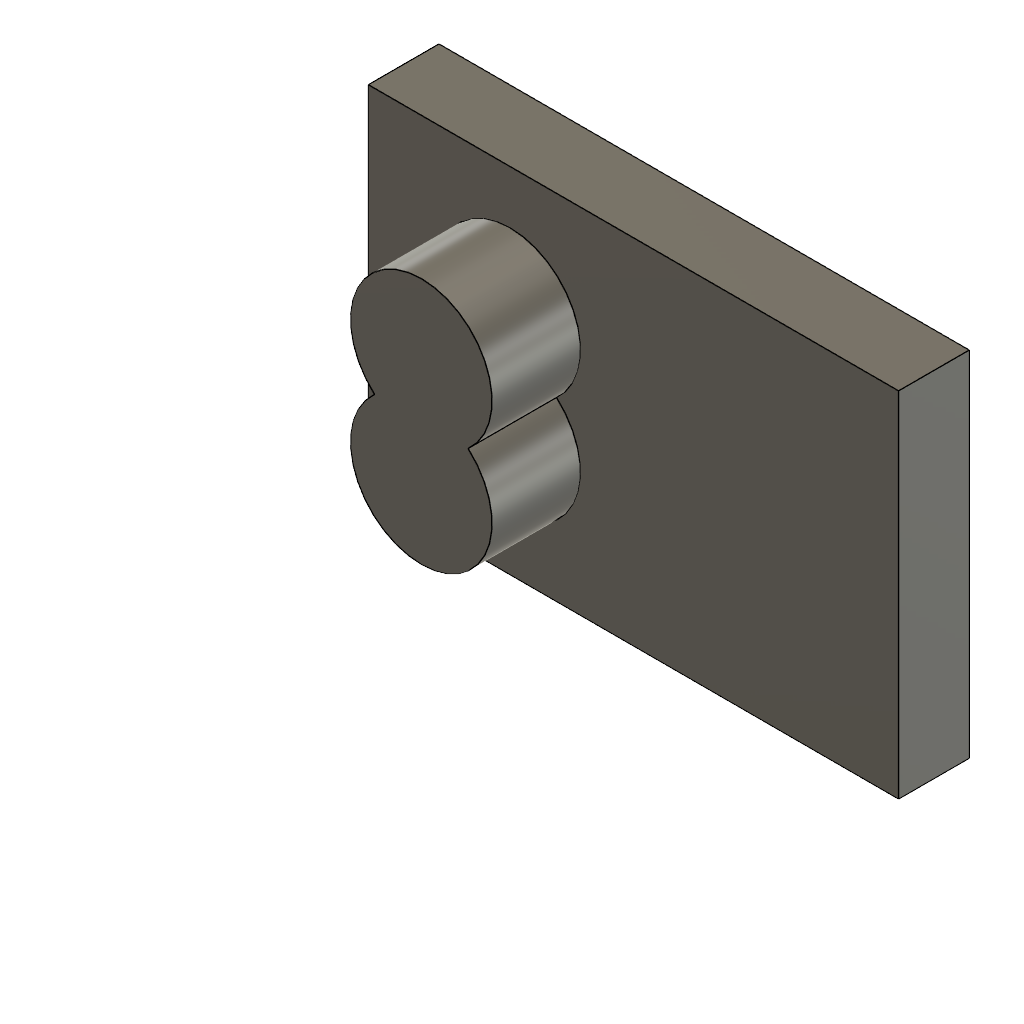
mirror_feature_mid_plane (Autodesk Fusion 360 design; units mm, degrees)
part number: 2026-11-13-14-45-39-169
Autodesk Fusion 360 part; units mm, degrees
sketch "Sketch1" plane through (0, 0, 0) normal (0, 0, 1) x (1, 0, 0)
  line L0 (0, 0) -> (30, 0)
  line L1 (30, 0) -> (30, 20)
  line L2 (30, 20) -> (0, 20)
  line L3 (0, 20) -> (0, 0)
extrude "Extrude1" add sketch "Sketch1" along normal blind 4
sketch "Sketch2" plane through (0, 0, 4) normal (0, 0, 1) x (1, 0, 0)
  line L0 (0, 20) -> (0, 0)
  line L1 (0, 0) -> (30, 0)
  line L2 (30, 0) -> (30, 20)
  line L3 (30, 20) -> (0, 20)
  circle A0 centre (8, 7) radius 4
extrude "Extrude2" add sketch "Sketch2" along normal blind 5 contours A0
ref_plane "WorkPlane1" through (0, 10, 0) normal (0, 1, 0) x (0, 0, 1)
mirror "Mirror1" about plane through (0, 10, 0) normal (0, 1, 0) of "Extrude2"
